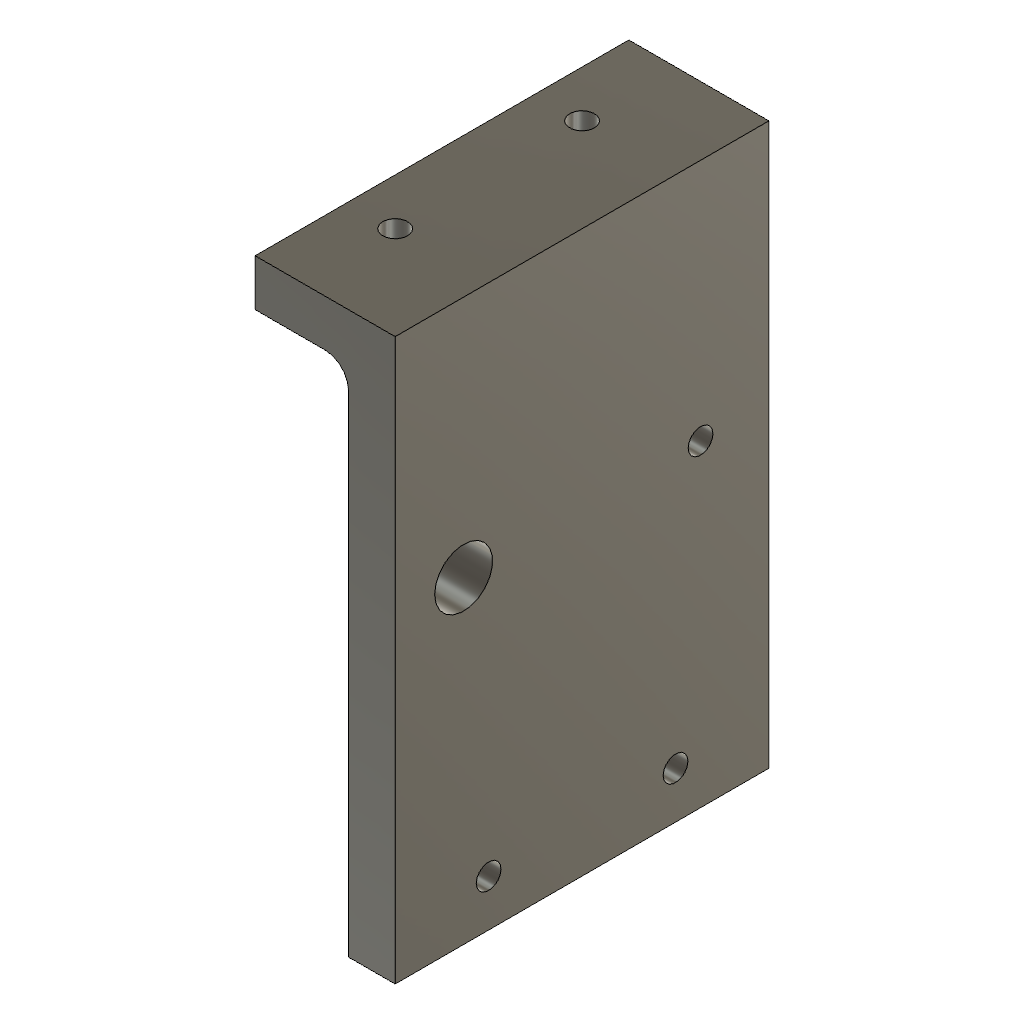
frame_plate_crank_side (Autodesk Fusion 360 design; units mm, degrees)
part number: 2026-10-05-14-06-25-879
Autodesk Fusion 360 part; units mm, degrees
sketch "Sketch1" plane through (0, 0, 0) normal (0, 1, 0) x (1, 0, 0)
  line L0 (0, 0) -> (40, 0)
  line L1 (40, 0) -> (40, -185)
  line L2 (40, -185) -> (20, -185)
  line L3 (20, -185) -> (20, -195)
  line L4 (0, 0) -> (0, 10)
  line L5 (0, 10) -> (50, 10)
  line L6 (50, 10) -> (50, -195)
  line L7 (20, -195) -> (50, -195)
  line L8 (40, -75) -> (50, -75)
  dimension "d1" = 40
  dimension "d2" = 185
  dimension "d3" = 20
  dimension "d4" = 10
  dimension "d5" = 10
  dimension "d6" = 50
  dimension "d42" = 85
  constraint coincident L0.start L4.start
  constraint horizontal L0
  constraint perpendicular L0 L1
  constraint perpendicular L1 L2
  constraint perpendicular L2 L3
  constraint perpendicular L0 L4
  constraint perpendicular L4 L5
  constraint perpendicular L5 L6
  constraint perpendicular L3 L7
  constraint coincident L1 L8.start
  constraint coincident L6 L8.end
  constraint perpendicular L6 L8
  measures "d1" distance of L0.start L0.end
  measures "d2" distance of L0.end L1.end
  measures "d3" distance of L1.end L2.end
  measures "d15" distance of L2.end L3.end
  measures "d5" distance of L0.start L4.end
  measures "d6" distance of L4.end L5.end
  measures "d42" distance of L5.end L8
extrude "Extrude1" add sketch "Sketch1" along normal blind 80 contours L1 L2 L3 L6 L7 L8
sketch "Sketch2" plane through (50, 0, 0) normal (1, 0, 0) x (0, 1, 0)
  line L0 (0, 195) -> (0, 75)
  line L1 (80, 75) -> (80, 195)
  line L2 (80, 195) -> (0, 195)
  line L3 (0, 143) -> (80, 143) construction
  circle A0 centre (14.65, 143) radius 6.2
  circle A1 centre (65.35, 143) radius 2.65
  line L4 (0, 75) -> (80, 75)
  line L5 (0, 85) -> (80, 85) construction
  circle A2 centre (20, 85) radius 2.65
  circle A3 centre (60, 85) radius 2.65
  dimension "d10" = 12.4
  dimension "d11" = 5.3
  dimension "d12" = 50.7
  dimension "d13" = 14.65
  dimension "d43" = 52
  dimension "d44" = 10
  dimension "d45" = 5.3
  dimension "d46" = 5.3
  dimension "d47" = 20
  dimension "d48" = 20
  constraint coincident L0 L3.start
  constraint coincident L1 L3.end
  constraint perpendicular L1 L3
  constraint coincident L3 A0.centre
  constraint coincident L3 A1.centre
  constraint coincident L0 L5.start
  constraint coincident L1 L5.end
  constraint perpendicular L1 L5
  constraint coincident L5 A2.centre
  constraint coincident L5 A3.centre
  measures "d10" diameter of A0
  measures "d11" diameter of A1
  measures "d12" distance of A0.centre A1.centre
  measures "d13" distance of L3.start A0.centre
  measures "d43" distance of L2 A0.centre
  measures "d44" distance of L4 L5
  measures "d45" diameter of A2
  measures "d46" diameter of A3
  measures "d47" distance of L5.start A2.centre
  measures "d48" distance of L1 A3.centre
extrude "Extrude2" cut sketch "Sketch2" against normal blind 10 contours A0 | A1 | A2 | A3
sketch "Sketch3" plane through (0, 0, 195) normal (0, 0, 1) x (-1, 0, 0)
  line L0 (-20, 0) -> (-50, 0)
  line L1 (-50, 0) -> (-50, -80)
  line L2 (-50, -80) -> (-20, -80)
  line L3 (-20, -80) -> (-20, 0)
  line L4 (-30, -79.8441) -> (-30, -0.127) construction
  circle A0 centre (-30, -60) radius 2.65
  circle A1 centre (-30, -20) radius 2.65
  dimension "d16" = 5.3
  dimension "d17" = 5.3
  dimension "d18" = 20
  dimension "d19" = 20
  dimension "d22" = 10
  constraint coincident L4 A0.centre
  constraint coincident L4 A1.centre
  constraint vertical L4
  measures "d16" diameter of A0
  measures "d17" diameter of A1
  measures "d18" distance of L0 A1.centre
  measures "d19" distance of L2 A0.centre
  measures "d22" horizontal distance of L0.start L4.end
extrude "Extrude3" cut sketch "Sketch3" against normal blind 10 contours A0 | A1
fillet "Fillet7" radius 5 1 edges at (40, 40, 185)
equation "Scale_factor = 1 mm"
